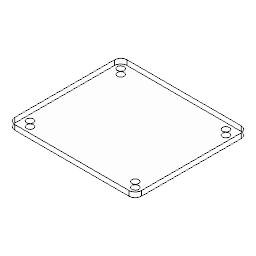
air_quality_sensor_particle_sensor_addon_Assembly (Autodesk Fusion 360 archive; units mm, degrees)
design "air_quality_sensor_glass_top"
Autodesk Fusion 360 part; units mm, degrees
sketch "Sketch10" plane through (0, 0, 0) normal (0, 0, 1) x (1, 0, 0)
  line L0 (0, 0) -> (45.72, 0)
  arc A0 (48.26, -2.54) -> (45.72, 0) centre (45.72, -2.54) ccw
  line L1 (45.72, -2.54) -> (48.26, -2.54) construction
  line L2 (45.72, -2.54) -> (45.72, 0) construction
  line L3 (48.26, -2.54) -> (48.26, -42.4361)
  arc A1 (48.26, -2.54) -> (45.72, 0) centre (45.72, -2.54) ccw
  arc A2 (45.72, -44.9761) -> (48.26, -42.4361) centre (45.72, -42.4361) ccw
  line L4 (0, -42.4361) -> (-2.54, -42.4361) construction
  line L5 (45.72, -44.9761) -> (0, -44.9761)
  arc A3 (-2.54, -42.4361) -> (0, -44.9761) centre (0, -42.4361) ccw
  arc A4 (-2.54, -42.4361) -> (0, -44.9761) centre (0, -42.4361) ccw
  line L6 (0, -42.4361) -> (0, -44.9761) construction
  arc A5 (0, 0) -> (-2.54, -2.54) centre (0, -2.54) ccw
  line L7 (-2.54, -42.4361) -> (-2.54, -2.54)
  point P0 (45.72, -44.9761)
  dimension "d5" = 45.72
  dimension "d7" = 2.54
  dimension "d8" = 90
  dimension "d9" = 39.8961
  dimension "d10" = 2.54
  dimension "d11" = 2.54
  dimension "d12" = 45.72
  dimension "d13" = 2.54
  dimension "d14" = 90
  dimension "d15" = 39.8961
  dimension "d16" = 2.54
  dimension "d17" = 2.54
  constraint coincident L0.start A5.start
  constraint horizontal L0
  constraint perpendicular L1 L3
  constraint coincident P0 A2.start
  constraint perpendicular L4 L7
  measures "d5" distance of L0.start L0.end
  measures "d7" radius of A0
  measures "d8" angle of L1 L2
  measures "d9" distance of A0.start L3.end
  measures "d10" radius of A1
  measures "d11" radius of A2
  measures "d12" distance of P0 L5.end
  measures "d13" radius of A4
  measures "d14" angle of L4 L6
  measures "d15" distance of L4.end A5.end
  measures "d16" radius of A3
  measures "d17" radius of A5
extrude "Extrude3" add sketch "Sketch10" along normal blind 2
sketch "Sketch11" plane through (0, 0, 2) normal (0, 0, 1) x (-1, 0, 0)
  arc A0 (-45.72, 44.9761) -> (-48.26, 42.4361) centre (-45.72, 42.4361) ccw
  line L0 (-48.26, 42.4361) -> (-48.26, 2.54)
  arc A1 (-48.26, 2.54) -> (-45.72, 0) centre (-45.72, 2.54) ccw
  line L1 (-45.72, 0) -> (0, 0)
  arc A2 (0, 0) -> (2.54, 2.54) centre (0, 2.54) ccw
  line L2 (2.54, 2.54) -> (2.54, 42.4361)
  arc A3 (2.54, 42.4361) -> (0, 44.9761) centre (0, 42.4361) ccw
  line L3 (0, 44.9761) -> (-45.72, 44.9761)
  circle A4 centre (-1.778, 4.318) radius 1.35
  dimension "d22" = 2.7
  measures "d22" diameter of A4
extrude "Extrude4" cut sketch "Sketch11" against normal blind 4 contours A4
sketch "Sketch12" plane through (0, 0, 2) normal (0, 0, 1) x (-1, 0, 0)
  circle A0 centre (-1.778, 4.318) radius 1.35
  arc A1 (-45.72, 44.9761) -> (-48.26, 42.4361) centre (-45.72, 42.4361) ccw
  line L0 (-48.26, 42.4361) -> (-48.26, 2.54)
  arc A2 (-48.26, 2.54) -> (-45.72, 0) centre (-45.72, 2.54) ccw
  line L1 (-45.72, 0) -> (0, 0)
  arc A3 (0, 0) -> (2.54, 2.54) centre (0, 2.54) ccw
  line L2 (2.54, 2.54) -> (2.54, 42.4361)
  arc A4 (2.54, 42.4361) -> (0, 44.9761) centre (0, 42.4361) ccw
  line L3 (0, 44.9761) -> (-45.72, 44.9761)
  circle A5 centre (-43.942, 4.318) radius 1.35
  dimension "d27" = 2.7
  measures "d27" diameter of A5
extrude "Extrude5" cut sketch "Sketch12" against normal blind 4 contours A5
sketch "Sketch13" plane through (0, 0, 2) normal (0, 0, 1) x (-1, 0, 0)
  circle A0 centre (-43.942, 4.318) radius 1.35
  circle A1 centre (-1.778, 4.318) radius 1.35
  arc A2 (-45.72, 44.9761) -> (-48.26, 42.4361) centre (-45.72, 42.4361) ccw
  line L0 (-48.26, 42.4361) -> (-48.26, 2.54)
  arc A3 (-48.26, 2.54) -> (-45.72, 0) centre (-45.72, 2.54) ccw
  line L1 (-45.72, 0) -> (0, 0)
  arc A4 (0, 0) -> (2.54, 2.54) centre (0, 2.54) ccw
  line L2 (2.54, 2.54) -> (2.54, 42.4361)
  arc A5 (2.54, 42.4361) -> (0, 44.9761) centre (0, 42.4361) ccw
  line L3 (0, 44.9761) -> (-45.72, 44.9761)
  circle A6 centre (-1.778, 40.6581) radius 1.35
  dimension "d32" = 2.7
  measures "d32" diameter of A6
extrude "Extrude6" cut sketch "Sketch13" against normal blind 4 contours A6
sketch "Sketch14" plane through (0, 0, 2) normal (0, 0, 1) x (-1, 0, 0)
  circle A0 centre (-1.778, 40.6581) radius 1.35
  circle A1 centre (-43.942, 4.318) radius 1.35
  circle A2 centre (-1.778, 4.318) radius 1.35
  arc A3 (-45.72, 44.9761) -> (-48.26, 42.4361) centre (-45.72, 42.4361) ccw
  line L0 (-48.26, 42.4361) -> (-48.26, 2.54)
  arc A4 (-48.26, 2.54) -> (-45.72, 0) centre (-45.72, 2.54) ccw
  line L1 (-45.72, 0) -> (0, 0)
  arc A5 (0, 0) -> (2.54, 2.54) centre (0, 2.54) ccw
  line L2 (2.54, 2.54) -> (2.54, 42.4361)
  arc A6 (2.54, 42.4361) -> (0, 44.9761) centre (0, 42.4361) ccw
  line L3 (0, 44.9761) -> (-45.72, 44.9761)
  circle A7 centre (-43.942, 40.6581) radius 1.35
  dimension "d37" = 2.7
  measures "d37" diameter of A7
extrude "Extrude7" cut sketch "Sketch14" against normal blind 4 contours A7
sketch "Sketch15" plane through (0, 0, 2) normal (0, 0, 1) x (-1, 0, 0)
  circle A0 centre (-43.942, 40.6581) radius 1.35
  circle A1 centre (-1.778, 40.6581) radius 1.35
  circle A2 centre (-43.942, 4.318) radius 1.35
  circle A3 centre (-1.778, 4.318) radius 1.35
  arc A4 (-45.72, 44.9761) -> (-48.26, 42.4361) centre (-45.72, 42.4361) ccw
  line L0 (-48.26, 42.4361) -> (-48.26, 2.54)
  arc A5 (-48.26, 2.54) -> (-45.72, 0) centre (-45.72, 2.54) ccw
  line L1 (-45.72, 0) -> (0, 0)
  arc A6 (0, 0) -> (2.54, 2.54) centre (0, 2.54) ccw
  line L2 (2.54, 2.54) -> (2.54, 42.4361)
  arc A7 (2.54, 42.4361) -> (0, 44.9761) centre (0, 42.4361) ccw
  line L3 (0, 44.9761) -> (-45.72, 44.9761)
  line L4 (-4.96, 7.5) -> (-40.76, 7.5)
  line L5 (-40.76, 7.5) -> (-40.76, 37.4761)
  line L6 (-40.76, 37.4761) -> (-4.96, 37.4761)
  line L7 (-4.96, 37.4761) -> (-4.96, 7.5)
  constraint horizontal L4
  constraint vertical L5
  constraint horizontal L6
  constraint vertical L7

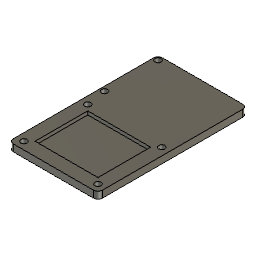
design "air_quality_sensor_holder_particle_sensor_addon"
Autodesk Fusion 360 part; units mm, degrees
sketch "Sketch10" plane through (0, 0, 0) normal (0, 0, 1) x (1, 0, 0)
  line L0 (0, 0) -> (45.72, 0)
  arc A0 (48.26, -2.54) -> (45.72, 0) centre (45.72, -2.54) ccw
  line L1 (45.72, -2.54) -> (48.26, -2.54) construction
  line L2 (45.72, -2.54) -> (45.72, 0) construction
  line L3 (48.26, -2.54) -> (48.26, -42.4361)
  arc A1 (48.26, -2.54) -> (45.72, 0) centre (45.72, -2.54) ccw
  arc A2 (45.72, -44.9761) -> (48.26, -42.4361) centre (45.72, -42.4361) ccw
  line L4 (0, -42.4361) -> (-2.54, -42.4361) construction
  line L5 (45.72, -44.9761) -> (0, -44.9761)
  arc A3 (-2.54, -42.4361) -> (0, -44.9761) centre (0, -42.4361) ccw
  arc A4 (-2.54, -42.4361) -> (0, -44.9761) centre (0, -42.4361) ccw
  line L6 (0, -42.4361) -> (0, -44.9761) construction
  arc A5 (0, 0) -> (-2.54, -2.54) centre (0, -2.54) ccw
  line L7 (-2.54, -42.4361) -> (-2.54, -2.54)
  point P0 (45.72, -44.9761)
  dimension "d5" = 45.72
  dimension "d7" = 2.54
  dimension "d8" = 90
  dimension "d9" = 39.8961
  dimension "d10" = 2.54
  dimension "d11" = 2.54
  dimension "d12" = 45.72
  dimension "d13" = 2.54
  dimension "d14" = 90
  dimension "d15" = 39.8961
  dimension "d16" = 2.54
  dimension "d17" = 2.54
  constraint coincident L0.start A5.start
  constraint horizontal L0
  constraint perpendicular L1 L3
  constraint coincident P0 A2.start
  constraint perpendicular L4 L7
  measures "d5" distance of L0.start L0.end
  measures "d7" radius of A0
  measures "d8" angle of L1 L2
  measures "d9" distance of A0.start L3.end
  measures "d10" radius of A1
  measures "d11" radius of A2
  measures "d12" distance of P0 L5.end
  measures "d13" radius of A4
  measures "d14" angle of L4 L6
  measures "d15" distance of L4.end A5.end
  measures "d16" radius of A3
  measures "d17" radius of A5
extrude "Extrude3" add sketch "Sketch10" along normal blind 4 makes body 1
sketch "Sketch11" plane through (0, 0, 4) normal (0, 0, 1) x (-1, 0, 0)
  arc A0 (-45.72, 44.9761) -> (-48.26, 42.4361) centre (-45.72, 42.4361) ccw
  line L0 (-48.26, 42.4361) -> (-48.26, 2.54)
  arc A1 (-48.26, 2.54) -> (-45.72, 0) centre (-45.72, 2.54) ccw
  line L1 (-45.72, 0) -> (0, 0)
  arc A2 (0, 0) -> (2.54, 2.54) centre (0, 2.54) ccw
  line L2 (2.54, 2.54) -> (2.54, 42.4361)
  arc A3 (2.54, 42.4361) -> (0, 44.9761) centre (0, 42.4361) ccw
  line L3 (0, 44.9761) -> (-45.72, 44.9761)
  circle A4 centre (-1.778, 4.318) radius 1.75
  dimension "d22" = 3.5
  measures "d22" diameter of A4
extrude "Extrude4" cut sketch "Sketch11" against normal blind 4 contours A4 bodies 1
sketch "Sketch12" plane through (0, 0, 4) normal (0, 0, 1) x (-1, 0, 0)
  circle A0 centre (-1.778, 4.318) radius 1.75
  arc A1 (-45.72, 44.9761) -> (-48.26, 42.4361) centre (-45.72, 42.4361) ccw
  line L0 (-48.26, 42.4361) -> (-48.26, 2.54)
  arc A2 (-48.26, 2.54) -> (-45.72, 0) centre (-45.72, 2.54) ccw
  line L1 (-45.72, 0) -> (0, 0)
  arc A3 (0, 0) -> (2.54, 2.54) centre (0, 2.54) ccw
  line L2 (2.54, 2.54) -> (2.54, 42.4361)
  arc A4 (2.54, 42.4361) -> (0, 44.9761) centre (0, 42.4361) ccw
  line L3 (0, 44.9761) -> (-45.72, 44.9761)
  circle A5 centre (-43.942, 4.318) radius 1.75
  dimension "d27" = 3.5
  measures "d27" diameter of A5
extrude "Extrude5" cut sketch "Sketch12" against normal blind 4 contours A5 bodies 1
sketch "Sketch13" plane through (0, 0, 4) normal (0, 0, 1) x (-1, 0, 0)
  circle A0 centre (-43.942, 4.318) radius 1.75
  circle A1 centre (-1.778, 4.318) radius 1.75
  arc A2 (-45.72, 44.9761) -> (-48.26, 42.4361) centre (-45.72, 42.4361) ccw
  line L0 (-48.26, 42.4361) -> (-48.26, 2.54)
  arc A3 (-48.26, 2.54) -> (-45.72, 0) centre (-45.72, 2.54) ccw
  line L1 (-45.72, 0) -> (0, 0)
  arc A4 (0, 0) -> (2.54, 2.54) centre (0, 2.54) ccw
  line L2 (2.54, 2.54) -> (2.54, 42.4361)
  arc A5 (2.54, 42.4361) -> (0, 44.9761) centre (0, 42.4361) ccw
  line L3 (0, 44.9761) -> (-45.72, 44.9761)
  circle A6 centre (-1.778, 40.6581) radius 1.75
  dimension "d32" = 3.5
  measures "d32" diameter of A6
extrude "Extrude6" cut sketch "Sketch13" against normal blind 4 contours A6 bodies 1
sketch "Sketch14" plane through (0, 0, 4) normal (0, 0, 1) x (-1, 0, 0)
  circle A0 centre (-1.778, 40.6581) radius 1.75
  circle A1 centre (-43.942, 4.318) radius 1.75
  circle A2 centre (-1.778, 4.318) radius 1.75
  arc A3 (-45.72, 44.9761) -> (-48.26, 42.4361) centre (-45.72, 42.4361) ccw
  line L0 (-48.26, 42.4361) -> (-48.26, 2.54)
  arc A4 (-48.26, 2.54) -> (-45.72, 0) centre (-45.72, 2.54) ccw
  line L1 (-45.72, 0) -> (0, 0)
  arc A5 (0, 0) -> (2.54, 2.54) centre (0, 2.54) ccw
  line L2 (2.54, 2.54) -> (2.54, 42.4361)
  arc A6 (2.54, 42.4361) -> (0, 44.9761) centre (0, 42.4361) ccw
  line L3 (0, 44.9761) -> (-45.72, 44.9761)
  circle A7 centre (-43.942, 40.6581) radius 1.75
  dimension "d37" = 3.5
  measures "d37" diameter of A7
extrude "Extrude7" cut sketch "Sketch14" against normal blind 4 contours A7 bodies 1
sketch "Sketch15" plane through (0, 0, 4) normal (0, 0, 1) x (-1, 0, 0)
  circle A0 centre (-43.942, 40.6581) radius 1.75
  circle A1 centre (-1.778, 40.6581) radius 1.75
  circle A2 centre (-43.942, 4.318) radius 1.75
  circle A3 centre (-1.778, 4.318) radius 1.75
  arc A4 (-45.72, 44.9761) -> (-48.26, 42.4361) centre (-45.72, 42.4361) ccw
  line L0 (-48.26, 42.4361) -> (-48.26, 2.54)
  arc A5 (-48.26, 2.54) -> (-45.72, 0) centre (-45.72, 2.54) ccw
  line L1 (-45.72, 0) -> (0, 0)
  arc A6 (0, 0) -> (2.54, 2.54) centre (0, 2.54) ccw
  line L2 (2.54, 2.54) -> (2.54, 42.4361)
  arc A7 (2.54, 42.4361) -> (0, 44.9761) centre (0, 42.4361) ccw
  line L3 (0, 44.9761) -> (-45.72, 44.9761)
  line L4 (-4.96, 7.5) -> (-40.76, 7.5)
  line L5 (-40.76, 7.5) -> (-40.76, 37.4761)
  line L6 (-40.76, 37.4761) -> (-4.96, 37.4761)
  line L7 (-4.96, 37.4761) -> (-4.96, 7.5)
  constraint horizontal L4
  constraint vertical L5
  constraint horizontal L6
  constraint vertical L7
extrude "Extrude8" cut sketch "Sketch15" against normal blind 2 contours L4 L5 L6 L7 bodies 1
sketch "outline" plane through (0, 0, 0) normal (0, 0, 1) x (1, 0, 0)
  line L0 (45.72, -44.9761) -> (0, -44.9761)
  line L1 (-2.54, -42.4361) -> (-2.54, -2.54)
  line L2 (48.26, -2.54) -> (48.26, -42.4361)
  line L3 (48.3, 40) -> (0.04, 40)
  arc A0 (-2.54, -42.4361) -> (0, -44.9761) centre (0, -42.4361) ccw
  line L4 (-2.5, 37.46) -> (-2.5, 6.98)
  line L5 (0, -44.9761) -> (45.72, -44.9761)
  line L6 (-2.54, -42.4361) -> (-2.5, 37.46)
  arc A1 (-2.54, -42.4361) -> (0, -44.9761) centre (0, -42.4361) ccw
  arc A2 (0.04, 40) -> (-2.5, 37.46) centre (0.04, 37.46) ccw
  line L7 (48.3, 4.44) -> (48.3, 40)
  arc A3 (48.3, 37.46) -> (45.76, 40) centre (45.76, 37.46) ccw
  line L8 (45.76, 40) -> (0.04, 40)
  arc A4 (45.72, -44.9761) -> (48.26, -42.4361) centre (45.72, -42.4361) ccw
  line L9 (48.26, -42.4361) -> (48.3, 37.46)
  circle A5 centre (1.778, -4.318) radius 1.75
  circle A6 centre (43.942, -4.318) radius 1.75
  circle A7 centre (43.942, -40.6581) radius 1.75
  circle A8 centre (1.778, -40.6581) radius 1.75
  circle A9 centre (0.04, 6.98) radius 1.75
  circle A10 centre (0.04, 37.46) radius 1.75
  dimension "d52" = 3.5
  dimension "d53" = 3.5
  constraint concentric A2 A10
  measures "d52" diameter of A9
  measures "d53" diameter of A10
extrude "Extrude12" add sketch "outline" along normal blind 4 separate body contours L0 L3 A0 L5 L6 A1 A2 A3 L8 A4 L9 makes body 2
extrude "Extrude13" cut sketch "Sketch15" against normal blind 2 contours L4 L5 L6 L7 bodies 2
hidden bodies 1

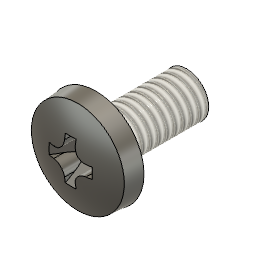
design "Binding Head Screw JIS B 1111 - M2.5x5 Steel 4.6 Plain"
description: Binding Head Screw JIS B 1111 - M2.5x5
part number: BHS JIS B 1111 - M2.5x5 Steel 4.6 Plain
Autodesk Fusion 360 part; units mm, degrees
sketch "Sketch1" plane through (0, 0, 0) normal (0, 1, 0) x (1, 0, 0)
  line L0 (0, -1.5) -> (0, 5)
  line L1 (-2.65, 0) -> (-2.5625, -1)
  line L2 (-2.65, 0) -> (-1.0691, 0)
  arc A0 (-2.5625, -1) -> (0, -1.5) centre (0, 5.3165) ccw
  line L3 (0, 5) -> (-1.25, 5)
  line L4 (-1.25, 5) -> (-1.25, 0.84)
  line L5 (-1.25, 0.84) -> (-1.0691, 0.165)
  line L6 (-1.0691, 0.165) -> (-1.0691, 0)
  dimension "d13" = 5
  dimension "d14" = 5.3
  dimension "d18" = 2.5
  dimension "d23" = 15
  dimension "d53" = 1.5
  dimension "d55" = 4.16
  dimension "d56" = 5
  dimension "d57" = 4.835
  dimension "d60" = 1
  constraint vertical L0
  constraint coincident origin L0
  constraint coincident origin L2
  constraint coincident L0 A0.end
  constraint coincident L0 A0.centre
  constraint coincident L0.start A0.end
  constraint perpendicular L3 L4
  constraint vertical L6
  constraint coincident L2.end L6.end
  measures "d13" angle of L0 L1
  measures "d23" angle of L4 L5
  measures "d53" distance of L0.start L2
  measures "d55" distance of L3 L4.end
  measures "d56" distance of L2 L3
  measures "d57" distance of L3 L5.end
  measures "d60" distance of L1.end L2
revolve "Revolve1" add sketch "Sketch1" angle 360 about axis through (0, 0, 1.5) along (0, 0, -1) makes body 1
fillet "Fillet2" radius 0.1 1 edges at (-0.9968, 0.3866, 0) on bodies 1
ref_plane "WorkPlane1" through (0, 0, 1.5) normal (0, 0, 1) x (1, 0, 0)
sketch "Sketch2" plane through (0, 0, 1.5) normal (0, 0, 1) x (1, 0, 0)
  line L0 (-0.296, 0.296) -> (-1.25, 0.296)
  line L1 (-1.25, 0.296) -> (-1.25, -0.296)
  line L2 (-1.25, -0.296) -> (-0.296, -0.296)
  line L3 (-0.296, -0.296) -> (-0.296, -1.25)
  line L4 (-0.296, -1.25) -> (0.296, -1.25)
  line L5 (0.296, -1.25) -> (0.296, -0.296)
  line L6 (0.296, -0.296) -> (1.25, -0.296)
  line L7 (1.25, -0.296) -> (1.25, 0.296)
  line L8 (1.25, 0.296) -> (0.296, 0.296)
  line L9 (0.296, 0.296) -> (0.296, 1.25)
  line L10 (0.296, 1.25) -> (-0.296, 1.25)
  line L11 (-0.296, 1.25) -> (-0.296, 0.296)
  dimension "d63" = 0.592
  dimension "d65" = 360
  dimension "d66" = 2.5
  constraint horizontal L0
  constraint perpendicular L0 L1
  constraint vertical L0.start L2.end
  constraint coincident L2.end L3.start
  measures "d63" distance of L0 L2
  measures "d66" distance of L1 L7
extrude "Extrude1" add sketch "Sketch2" against normal blind 1.32 separate body makes body 2
draft "Draft1" angle -30 neutral plane through (0, 0, 1.5) pull (0, 0, 1) 4 faces at (-0.0987, -1.25, 1.06) (1.25, -0.0987, 1.06) (0.0987, 1.25, 1.06) (-1.25, 0.0987, 1.06) on bodies 2
fillet "Fillet1" radius 0.592 4 edges at (0.296, -0.296, 0.84) (0.296, 0.296, 0.84) (-0.296, -0.296, 0.84) (-0.296, 0.296, 0.84) on bodies 2
combine "Combine1" operation cut target body 1 tool bodies 2
thread "Thread1" "ISO Metric profile 2.5 M2.5x0.45 M2.5x0.45 6g" major diameter 2.43 minor diameter 1.9165 pitch 0.45 angle 60 resizes the face on face at (-1.2438, -0.1245, -3.6133) on bodies 1
equation "adsk_nomdia = 2.50 mm"
equation "adsk_nomlen = 5.00 mm"
equation "adsk_headdia = 5.30 mm"
equation "adsk_baseh = 1.00 mm"
equation "adsk_phildia = 2.50 mm"
equation "adsk_midfillet = 0.10 mm"
equation "adsk_thrlen = 4.16 mm"
equation "adsk_phildepth = 1.32 mm"
equation "adsk_thrrun = 0.675 mm"
equation "adsk_thrang = 15.00 deg"
equation "adsk_headang = 5.00 deg"
equation "d13 = adsk_headang"
equation "d14 = adsk_headdia"
equation "adsk_ovalh = 0.50 mm"
equation "d18 = adsk_nomdia"
equation "d23 = adsk_thrang"
equation "d32 = adsk_baseh + adsk_ovalh"
equation "adsk_philwidth = 0.592 mm"
equation "d43 = -adsk_phildepth"
equation "d52 = adsk_midfillet"
equation "d53 = adsk_baseh + adsk_ovalh"
equation "d55 = adsk_thrlen"
equation "d56 = adsk_nomlen"
equation "d57 = adsk_thrlen + adsk_thrrun"
equation "d60 = adsk_baseh"
equation "d63 = adsk_philwidth"
equation "d66 = adsk_phildia"
equation "d68 = adsk_philwidth"
